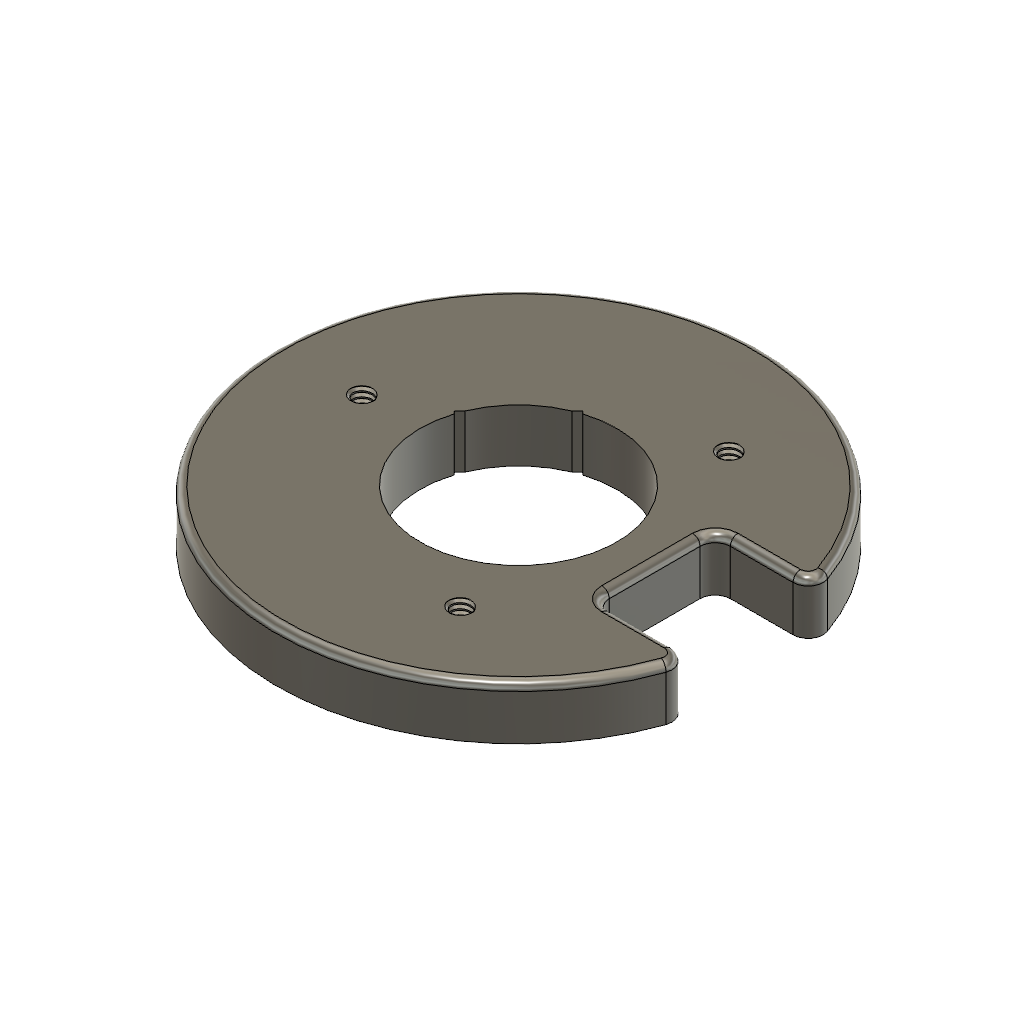
Knob Assembly (Autodesk Fusion 360 archive; units mm, degrees)
design "Motor Mout Fixture"
Autodesk Fusion 360 part; units mm, degrees
sketch "Sketch1" plane through (0, 0, 0) normal (0, 1, 0) x (1, 0, 0)
  circle A0 centre (0, 0) radius 16
  circle A1 centre (0, 0) radius 10.25
  line L0 (9, 4) -> (9, -4)
  line L1 (9, -4) -> (15.4919, -4)
  line L2 (9, 4) -> (15.4919, 4)
  point P0 (-10.25, 0)
  point P1 (5.125, -8.8768)
  point P2 (5.125, 8.8768)
  dimension "d1" = 32
  dimension "d2" = 20.5
  dimension "d4" = 360
  constraint coincident A0.centre A1.centre
  constraint coincident A1 P0
  constraint vertical L0
  constraint coincident A0 L1.end
  constraint perpendicular L0 L1
  constraint coincident A0 L2.end
  constraint perpendicular L0 L2
  measures "d1" diameter of A0
  measures "d2" diameter of A1
extrude "Extrude1" add sketch "Sketch1" against normal blind 3.5 contours A0 A1 L1 L2 | A1 L0 L1 L2 picked at (12.606, 6.1973) picked at (2.5927, -0.2529)
hole "Hole1" at (5.125, 0, -8.8768) at (-10.25, 0, 0) at (5.125, 0, 8.8768) direction (0, -1, 0) diameter 1.271 end up to surface (3.5 mm away)
thread "Thread1" "ISO Metric profile 1.6 M1.6x0.35 M1.6x0.35 6H" major diameter 1.668 minor diameter 1.271 pitch 0.35 angle 60 modelled right hand crest width 0.0916 on face at (-10.1867, -1.1667, 0.6323) crest through (-10.25, -0.0875, 0.6355) on face at (5.1883, -1.1667, -8.2444) crest through (5.125, -0.0875, -8.2413) on face at (5.1567, -2.3333, 9.5115) crest through (5.125, -0.0875, 9.5123)
sketch "Sketch2" plane through (0, 0, 0) normal (0, 1, 0) x (1, 0, 0)
  line L0 (0, 0) -> (3.5355, -3.5355)
  line L1 (0, 0) -> (5, 0) construction
  line L2 (0, 0) -> (-4.2426, 4.2426)
  line L3 (0, 0) -> (6, 0) construction
  line L4 (0, 0) -> (-2.1213, -2.1213)
  line L5 (0, 0) -> (2.1213, 2.1213)
  line L6 (-2.1213, -2.1213) -> (-6.364, 2.1213)
  line L7 (-6.364, 2.1213) -> (-4.2426, 4.2426)
  line L8 (-2.1213, -2.1213) -> (1.7678, -6.0104)
  line L9 (3.5355, -3.5355) -> (1.4142, -5.6569)
  line L10 (3.5355, -3.5355) -> (-4.2426, 4.2426)
  line L11 (-4.2426, 4.2426) -> (-2.1213, 6.364)
  line L12 (-2.1213, 6.364) -> (5.6569, -1.4142)
  line L13 (5.6569, -1.4142) -> (3.5355, -3.5355)
  circle A0 centre (0, 0) radius 6.5
  dimension "d11" = 5
  dimension "d12" = 45
  dimension "d13" = 135
  dimension "d14" = 6
  dimension "d15" = 3
  dimension "d21" = 13
  constraint horizontal L1
  constraint coincident L0.start L1.start
  constraint horizontal L3
  constraint perpendicular L0 L4
  constraint perpendicular L2 L5
  constraint perpendicular L4 L6
  constraint perpendicular L2 L7
  constraint perpendicular L4 L8
  constraint coincident L8 L9.end
  constraint perpendicular L8 L9
  constraint perpendicular L10 L11
  constraint parallel L10 L12
  constraint parallel L11 L13
  measures "d11" distance of L0.start L0.end
  measures "d12" angle of L0 L1
  measures "d13" angle of L2 L3
  measures "d14" distance of L0.start L2.end
  measures "d15" distance of L0.start L4.end
  measures "d21" diameter of A0
extrude "Extrude2" cut sketch "Sketch2" against normal up to surface (3.5 mm away)
fillet "Fillet1" radius 1 4 edges at (9, -1.75, 4) (15.4919, -1.75, 4) (9, -1.75, -4) (15.4919, -1.75, -4)
fillet "Fillet2" radius 0.5 8 edges at (14.9586, 0, -4.4226) (12.0711, 0, -4) (9.2929, 0, -3.7071) (9, 0, 0) (9.2929, 0, 3.7071) (12.0711, 0, 4) (14.9586, 0, 4.4226) (-16, 0, 0)
